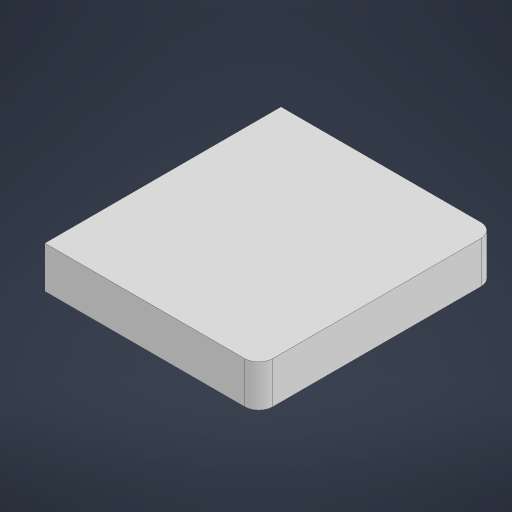
# Autodesk Inventor part: Верхняя основа v2
Saved by Autodesk Inventor 2024 (Build 280153000, 153)
## iProperties
Created: 2026-05-29
Part Number: Верхняя основа v2
Material: Типовые
Document SubType Name: Modeling
Designer: mitm
Density: 1 g/cm^3
Appearance: По умолчанию
Author: mitm
Autodesk Inventor part; units mm, degrees
ref_plane "YZ Plane" through (0, 0, 0) normal (1, 0, 0) x (0, 1, 0)
ref_plane "XZ Plane" through (0, 0, 0) normal (0, 1, 0) x (-1, 0, 0)
ref_plane "XY Plane" through (0, 0, 0) normal (0, 0, 1) x (1, 0, 0)
sketch "Эскиз1" plane through (0, 0, 0) normal (0, 1, 0) x (-1, 0, 0)
  line L0 (19.7795, 40.5) -> (-19.7795, 40.5)
  line L1 (-19.7795, -40.5) -> (19.7795, -40.5)
  line L2 (27.5, 42.5) -> (-27.5, 42.5)
  line L3 (-27.5, -42.5) -> (27.5, -42.5)
  line L4 (-27.5, -42.5) -> (-44.5, -42.5)
  line L5 (-49.5, -37.5) -> (-49.5, 37.5)
  line L6 (-44.5, 42.5) -> (-27.5, 42.5)
  line L7 (-47.5, -33) -> (-47.5, 33)
  line L8 (-27.5, 40.5) -> (-42.5, 40.5)
  line L9 (-47.5, 35.5) -> (-47.5, 33)
  line L10 (-27.5, -40.5) -> (-42.5, -40.5)
  line L11 (-47.5, -35.5) -> (-47.5, -33)
  circle A0 centre (-43.75, 36.75) radius 1.5
  circle A1 centre (-43.75, -36.75) radius 1.5
  arc A2 (-42.5, 40.5) -> (-47.5, 35.5) centre (-42.5, 35.5) ccw
  arc A3 (-44.5, 42.5) -> (-49.5, 37.5) centre (-44.5, 37.5) ccw
  arc A4 (-47.5, -35.5) -> (-42.5, -40.5) centre (-42.5, -35.5) ccw
  arc A5 (-49.5, -37.5) -> (-44.5, -42.5) centre (-44.5, -37.5) ccw
  line L12 (25.5, 40.5) -> (-25.5, 40.5)
  line L13 (-25.5, -40.5) -> (25.5, -40.5)
  line L14 (-27.5, 40.5) -> (-35, 40.5)
  line L15 (-47.5, 33) -> (-43.5, 33)
  line L16 (-37.5, 40.5) -> (-33.5, 40.5)
  line L17 (-37.5, 40.5) -> (-41.5, 40.5)
  line L18 (-41.5, 40.5) -> (-41.5, 35)
  arc A6 (-43.5, 33) -> (-41.5, 35) centre (-43.5, 35) ccw
  line L19 (-37.5, -40.5) -> (-33.5, -40.5)
  line L20 (-33.5, -40.5) -> (-41.5, -40.5)
  line L21 (-41.5, -40.5) -> (-41.5, -35)
  line L22 (-43.5, -33) -> (-47.5, -33)
  arc A7 (-41.5, -35) -> (-43.5, -33) centre (-43.5, -35) ccw
  line L23 (-27.5, 40.5) -> (-25.5, 40.5)
  line L24 (-25.5, -40.5) -> (-27.5, -40.5)
  line L25 (-41.5, -40.5) -> (13.5, -40.5)
  line L26 (13.5, 40.5) -> (-41.5, 40.5)
  line L27 (-41.5, 40.5) -> (-41.5, -40.5)
  line L28 (27.5, 40.5) -> (25.5, 40.5)
  line L29 (27.5, -40.5) -> (25.5, -40.5)
  line L30 (27.5, 0) -> (27.5, -40.5)
  line L31 (27.5, 0) -> (27.5, 40.5)
  line L32 (27.5, 40.5) -> (27.5, 42.5)
  line L33 (27.5, -40.5) -> (27.5, -42.5)
  line L34 (27.5, 42.5) -> (25.5, 42.5)
  line L35 (25.5, 42.5) -> (25.5, -42.5)
  line L36 (-41.5, 0) -> (-39.5, 0)
  line L37 (-39.5, 0) -> (-39.5, -40.5)
  line L38 (-39.5, 0) -> (-39.5, 40.5)
  line L39 (-39.5, -40.5) -> (15.5, -40.5)
  line L40 (15.5, -40.5) -> (15.5, 40.5)
  circle A8 centre (20.5, 35.5) radius 5
  circle A9 centre (20.5, -35.5) radius 5
  circle A10 centre (20.5, 35.5) radius 2.5
  circle A11 centre (20.5, -35.5) radius 2.5
  point P0 (0, 0)
  point P1 (-49.5, -42.5)
  point P2 (-47.5, -40.5)
  point P3 (-41.5, -33)
  dimension "d116" = 2
  dimension "d117" = 55
  dimension "d118" = 5
  dimension "d119" = 5
  constraints: 82 end point, 21 point on line, 18 tangent, 12 centre point, 12 point on circle, 8 equal length, 7 horizontal, 7 perpendicular, 3 equal radius, 2 coincident, 1 midpoint, 1 vertical
  measures "d116" distance of L36.start L36.end
  measures "d117" distance of L37.end L39.end
  measures "d118" diameter of A10
  measures "d119" diameter of A11
extrude "Выдавливание20" add sketch "Эскиз1" along normal blind 2 contours L12 A8 L40 L0 | L0 L12 L23 L8 A2 L9 L7 L11 A4 L10 L24 L13 L1 L35 L3 L4 A5 L5 A3 L6 L2 | L40 L1 L13 L24 L10 L37 L38 L8 L23 L12 L0 | L12 L35 A8 | A8 | A8 L35 A9 L40 | L35 L2 L32 L28 | L28 L31 L30 L29 L35 | A9 L13 L1 L40 | A9 | L35 L13 A9 | L29 L33 L3 L35 | L38 L36 L27 L18 L8 | L18 A6 L15 L9 A2 L8 | L37 L10 L21 L27 L36 | L27 A7 L22 L7 L15 A6 | L21 L10 A4 L11 L22 A7 | A0 | A1 | A10 | A11
extrude "Выдавливание21" add sketch "Эскиз1" against normal blind 13 contours L12 A8 L40 L0 | L0 L12 L23 L8 A2 L9 L7 L11 A4 L10 L24 L13 L1 L35 L3 L4 A5 L5 A3 L6 L2 | L12 L35 A8 | A8 | A8 L35 A9 L40 | L35 L2 L32 L28 | L28 L31 L30 L29 L35 | A9 L13 L1 L40 | A9 | L35 L13 A9 | L29 L33 L3 L35 | L38 L36 L27 L18 L8 | L18 A6 L15 L9 A2 L8 | L37 L10 L21 L27 L36 | L21 L10 A4 L11 L22 A7
sketch "Эскиз13" plane through (-27.5, 2, -42.5) normal (-1, 0, 0) x (0, 0, 1)
  line L0 (0, -15) -> (0, 0) projected
  line L1 (80, 0) -> (5, 0) projected
  line L2 (0, -15) -> (42.5, -15)
  line L3 (42.5, -15) -> (42.5, 0)
  line L4 (42.5, 0) -> (0, 0)
  line L5 (0, 0) -> (0, -15)
  line L6 (38.5, -11) -> (4, -11)
  line L7 (4, -11) -> (4, -4)
  line L8 (4, -4) -> (38.5, -4)
  line L9 (38.5, -4) -> (38.5, -11)
  point P0 (42.5, -2)
  dimension "d124" = 4
  constraints: 16 end point, 4 parallel, 2 perpendicular, 1 horizontal, 1 midpoint, 3 other
  measures "d124" distance between parallel lines of L2 L6
extrude "Выдавливание22" cut sketch "Эскиз13" against normal blind 13 contours L6 L7 L8 L9
sketch "Эскиз14" plane through (-15.5, -13, 40.5) normal (1, 0, 0) x (0, 0, -1)
  line L0 (44.5, 11) -> (79, 11) projected
  line L1 (44.5, 11) -> (4.5, 11)
  line L2 (4.5, 11) -> (4.5, 3)
  line L3 (4.5, 3) -> (44.5, 3)
  line L4 (44.5, 3) -> (44.5, 11)
  point P0 (40.5, 13)
  dimension "d127" = 40
  dimension "d128" = 8
  constraints: 8 end point, 2 parallel, 1 horizontal, 1 perpendicular
  measures "d127" distance of L3.end L2.end
  measures "d128" distance of L2.end L1.end
extrude "Выдавливание23" cut sketch "Эскиз14" against normal blind 2
sketch "Эскиз16" plane through (44.5, 2, -42.5) normal (0, 0, -1) x (-1, 0, 0)
  line L0 (0, -15) -> (72, -15) projected
  line L1 (72, 0.0571) -> (72, -15)
  circle A0 centre (77, -12) radius 5
  circle A1 centre (77, -12) radius 2.5
  arc A2 (72, 0.0571) -> (77, -7) centre (79.4803, 0.0571) ccw
  arc A3 (73.3767, -15.4455) -> (72, -15) centre (72.3109, -16.3891) ccw
  line L2 (72, -15) -> (72, 0.0571)
  point P0 (44.5, -2)
  constraints: 6 point on circle, 4 centre point, 4 end point, 1 coincident, 1 collinear, 1 tangent
extrude "Выдавливание27" add sketch "Эскиз16" against normal blind 20
extrude "Выдавливание28" cut sketch "Эскиз16" against normal blind 10
extrude "Выдавливание29" add sketch "Эскиз16" against normal blind 75
extrude "Выдавливание30" cut sketch "Эскиз16" against normal blind 65
extrude "Выдавливание31" add sketch "Эскиз16" against normal blind 20
extrude "Выдавливание32" cut sketch "Эскиз16" against normal blind 10
sketch "Эскиз17" plane through (-27.5, -13, 22.5) normal (-1, 0, 0) x (0, 0, 1)
  line L0 (20, 0) -> (10, 0) projected
  line L1 (-65, 15) -> (-55, 15) projected
  line L2 (20, 0) -> (-65, 0)
  line L3 (-65, 0) -> (-65, 15)
  line L4 (-65, 15) -> (20, 15)
  line L5 (20, 15) -> (20, 0)
  line L6 (0.0363, 0) -> (-44.9968, 0)
  line L7 (-44.9968, 0) -> (-44.9968, 15)
  line L8 (-44.9968, 15) -> (0.0363, 15)
  line L9 (0.0363, 15) -> (0.0363, 0)
  line L10 (20, 15) -> (-65.5188, 15)
  line L11 (-65.5188, 15) -> (-65.5188, 24.8462)
  line L12 (-65.5188, 24.8462) -> (20, 24.8462)
  line L13 (20, 24.8462) -> (20, 15)
  line L14 (0.0363, 0) -> (-44.9968, 15)
  line L15 (-44.9968, 0) -> (0.0363, 15)
  line L16 (-45, 11) -> (-26.5, 11) projected
  line L17 (-6.5773, 4) -> (-38.3833, 4)
  line L18 (-41.3833, 7) -> (-41.3833, 8)
  line L19 (-38.3833, 11) -> (-6.5773, 11)
  line L20 (-3.5773, 8) -> (-3.5773, 7)
  line L21 (-3.5773, 4) -> (-41.3833, 11) construction
  line L22 (-41.3833, 4) -> (-3.5773, 11) construction
  arc A0 (-6.5773, 4) -> (-3.5773, 7) centre (-6.5773, 7) ccw
  arc A1 (-3.5773, 8) -> (-6.5773, 11) centre (-6.5773, 8) ccw
  arc A2 (-41.3833, 7) -> (-38.3833, 4) centre (-38.3833, 7) ccw
  arc A3 (-38.3833, 11) -> (-41.3833, 8) centre (-38.3833, 8) ccw
  point P0 (-22.5, 13)
  point P1 (-22.4803, 7.5)
  dimension "d169" = 3
  constraints: 40 end point, 11 point on line, 8 parallel, 8 point on circle, 8 tangent, 4 centre point, 4 horizontal, 4 perpendicular, 3 equal radius, 3 midpoint
  measures "d169" radius of A0
extrude "Выдавливание33" cut sketch "Эскиз17" along normal blind 10 contours L4 L1 L10 L11 L12 L13
extrude "Выдавливание34" add sketch "Эскиз17" against normal blind 12 contours L0 L2 L9 L4 L5 | L14 L17 A0 L20 A1 L19 L15 L9 | L2 L15 L17 L14 | L15 L19 L16 L14 L4 | L2 L3 L1 L4 L7 | L7 L16 A3 L18 A2 L17 L15 | L17 L15 L14 | L14 L15 L19 A1 L20 A0 L17 | L14 L16 L7 | L15 L14 L16 L19 | L17 A2 L18 A3 L16 L14 L15
extrude "Выдавливание35" cut sketch "Эскиз17" against normal blind 12 contours L17 L15 L14 | L14 L15 L19 A1 L20 A0 L17 | L15 L14 L16 L19 | L17 A2 L18 A3 L16 L14 L15
